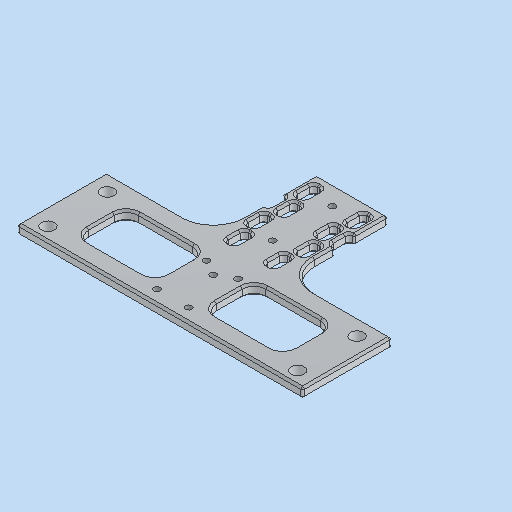
# Autodesk Inventor part: MM0948AN110_G01_101
Saved by Autodesk Inventor 2023.3 (Build 273359000, 359)
## iProperties
Created: 2024-06-12
Part Number: MM0948AN110_G01_101
Material: 3.3547 AlMg4,5Mn0,7 - AW 5083
Description: =<RBPARTNOTITLE2>
Document SubType Name: Modeling
Designer: RIC7AN
Mass: 28.6578 g
Surface Area: 161.617 cm^2
Volume: 28.6578 cm^3
Density: 1 g/cm^3
Appearance: Aluminium AnP
RBPARTMADEOF: 5 x 97 x 144 (FM)
RBDRAWINGMISSINGSPEC: --
AnP_Kategorie: 1
RBPARTNOTITLE2: Anfertigungsteil
RBSURFACE: anodised colourless
RBPARTNOTITLE1: manufactured part
RBSURFACE2: eloxiert farblos
AnP_Material: =<Material>
RBMATERIAL: =<Material>
RBMATNO: =<Part Number>
RBPARTNO: SIEHE MNR
MaxAbmaße: 5 x 97 x 144 (FM)
Author: RIC7AN
Keywords: =<RBPARTMADEOF>
Comments: =<RBSURFACE2>
Revision Number: 01
Autodesk Inventor part; units mm, degrees
ref_plane "YZ Plane" through (0, 0, 0) normal (1, 0, 0) x (0, 1, 0)
ref_plane "XZ Plane" through (0, 0, 0) normal (0, 1, 0) x (-1, 0, 0)
ref_plane "XY Plane" through (0, 0, 0) normal (0, 0, 1) x (1, 0, 0)
sketch "Skizze1" plane through (0, 0, 0) normal (0, 0, 1) x (1, 0, 0)
  line L0 (-72, 45) -> (72, 45)
  line L1 (72, 45) -> (72, 0)
  line L2 (72, 0) -> (-72, 0)
  line L3 (-72, 0) -> (-72, 45)
  line L4 (18, 45) -> (-18, 45)
  line L5 (-18, 45) -> (-18, 97)
  line L6 (-18, 97) -> (18, 97)
  line L7 (18, 97) -> (18, 45)
  line L8 (0, 116.4) -> (0, -19.4) projected
  line L9 (-100.8, 0) -> (100.8, 0) projected
  line L10 (-18, 80) -> (-15.5, 80)
  line L11 (-15.5, 80) -> (-15.5, 70)
  line L12 (-15.5, 70) -> (-18, 70)
  line L13 (-18, 70) -> (-18, 80)
  line L14 (18, 80) -> (15.5, 80)
  line L15 (15.5, 80) -> (15.5, 70)
  line L16 (15.5, 70) -> (18, 70)
  line L17 (18, 70) -> (18, 80)
  point P0 (0, 0)
  point P1 (-18, 45)
  point P2 (-15.5, 75)
  dimension "d0" = 144
  dimension "d1" = 45
  dimension "d2" = 52
  dimension "d3" = 36
  dimension "d65" = 2.5
  dimension "d66" = 10
  dimension "d67" = 22
  constraints: 32 end point, 8 parallel, 4 horizontal, 4 perpendicular, 3 collinear, 3 point on line, 1 midpoint, 3 other
  measures "d0" distance of L1.end L2.end
  measures "d1" distance of L2.end L0.start
  measures "d2" distance of L6.end L4.start
  measures "d3" distance of L5.end L6.end
  measures "d65" distance of L10.start L10.end
  measures "d66" distance of L10.end L11.end
  measures "d67" distance from line of L6 point (-15.5, 75)
extrude "Extrusion1" add sketch "Skizze1" along normal blind 5 contours L0 L8 L2 L3 | L5 L12 L11 L10 L6 L8 L0 | L8 L6 L7 L14 L15 L16 L0 | L0 L1 L2 L8
fillet "Rundung1" radius 15 2 edges at (-18, 45, 2.5) (18, 45, 2.5)
sketch "Skizze2" plane through (0, 0, 5) normal (0, 0, 1) x (1, 0, 0)
  line L0 (0, 116.4) -> (0, -19.4) projected
  line L1 (-33, 45) -> (-72, 45) projected
  point P0 (0, 0)
  point P1 (-63, 36.5)
  point P2 (-63, 6.5)
  point P3 (63, 36.5)
  point P4 (63, 6.5)
  dimension "d10" = 30
  dimension "d11" = 126
  dimension "d69" = 8.5
  constraints: 2 symmetric about line, 2 vertical alignment
  measures "d10" distance of point (-63, 6.5) point (-63, 36.5)
  measures "d11" distance of point (63, 36.5) point (-63, 36.5)
  measures "d69" distance from line of point (-63, 36.5) L1
hole "Bohrung1" at (-63, 36.5, 5) at (-63, 6.5, 5) at (63, 36.5, 5) at (63, 6.5, 5) direction (0, 0, -1) diameter 6.6 end through all clearance for "Inbusschraube ISO 4762  versenkt" size "M6" standard "ISO"
sketch "Skizze3" plane through (0, 0, 5) normal (0, 0, 1) x (1, 0, 0)
  line L0 (0, 116.4) -> (0, -19.4) projected
  line L1 (18, 97) -> (-18, 97) projected
  point P0 (0, 0)
  point P1 (0, 87)
  point P2 (0, 57)
  point P3 (0, 27)
  dimension "d21" = 30
  dimension "d22" = 30
  dimension "d70" = 10
  constraints: 3 point on line
  measures "d21" distance of point (0, 57) point (0, 87)
  measures "d22" distance of point (0, 27) point (0, 57)
  measures "d70" distance from line of point (0, 87) L1
hole "Bohrung2" at (0, 87, 5) at (0, 57, 5) at (0, 27, 5) direction (0, 0, -1) diameter 3.242 end through all thread size "M4x0.7" designation "M4" class "6H" standard "ISO Metric profile"
sketch "Skizze4" plane through (0, 0, 5) normal (0, 0, 1) x (1, 0, 0)
  line L0 (-15, 92.5) -> (-10, 92.5)
  line L1 (-10, 92.5) -> (-10, 82.5)
  line L2 (-10, 82.5) -> (-15, 82.5)
  line L3 (-15, 82.5) -> (-15, 92.5)
  line L4 (10, 92.5) -> (15, 92.5)
  line L5 (15, 92.5) -> (15, 82.5)
  line L6 (15, 82.5) -> (10, 82.5)
  line L7 (10, 82.5) -> (10, 92.5)
  line L8 (15, 67.5) -> (10, 67.5)
  line L9 (10, 67.5) -> (10, 57.5)
  line L10 (10, 57.5) -> (15, 57.5)
  line L11 (15, 57.5) -> (15, 67.5)
  line L12 (-10, 67.5) -> (-15, 67.5)
  line L13 (-15, 67.5) -> (-15, 57.5)
  line L14 (-15, 57.5) -> (-10, 57.5)
  line L15 (-10, 57.5) -> (-10, 67.5)
  line L16 (0, 116.4) -> (0, -19.4) projected
  line L17 (-52, 35) -> (-12.5, 35)
  line L18 (-12.5, 35) -> (-12.5, 10)
  line L19 (-12.5, 10) -> (-52, 10)
  line L20 (-52, 10) -> (-52, 35)
  line L21 (12.5, 35) -> (52, 35)
  line L22 (52, 35) -> (52, 10)
  line L23 (52, 10) -> (12.5, 10)
  line L24 (12.5, 10) -> (12.5, 35)
  line L25 (-12.5, 80) -> (-7.5, 80)
  line L26 (-7.5, 80) -> (-7.5, 70)
  line L27 (-7.5, 70) -> (-12.5, 70)
  line L28 (-12.5, 70) -> (-12.5, 80)
  line L29 (12.5, 80) -> (7.5, 80)
  line L30 (7.5, 80) -> (7.5, 70)
  line L31 (7.5, 70) -> (12.5, 70)
  line L32 (12.5, 70) -> (12.5, 80)
  line L33 (-12.5, 55) -> (-7.5, 55)
  line L34 (-7.5, 55) -> (-7.5, 45)
  line L35 (-7.5, 45) -> (-12.5, 45)
  line L36 (-12.5, 45) -> (-12.5, 55)
  line L37 (7.5, 55) -> (12.5, 55)
  line L38 (12.5, 55) -> (12.5, 45)
  line L39 (12.5, 45) -> (7.5, 45)
  line L40 (7.5, 45) -> (7.5, 55)
  circle A0 centre (-63, 6.5) radius 3.3 projected
  line L41 (-72, 0) -> (72, 0) projected
  point P0 (0, 0)
  dimension "d30" = 20
  dimension "d31" = 5
  dimension "d32" = 10
  dimension "d34" = 15
  dimension "d35" = 10
  dimension "d40" = 25
  dimension "d45" = 5
  dimension "d46" = 10
  dimension "d48" = 10
  dimension "d49" = 15
  dimension "d50" = 15
  dimension "d51" = 2.5
  dimension "d55" = 86
  dimension "d71" = 25
  dimension "d72" = 39.5
  dimension "d73" = 10
  constraints: 80 end point, 20 parallel, 12 collinear, 10 horizontal, 10 perpendicular, 3 point on line, 9 other
  measures "d30" distance between parallel lines of L7 L1
  measures "d31" distance of L0.start L0.end
  measures "d32" distance of L2.end L0.start
  measures "d34" distance between parallel lines of L12 L2
  measures "d35" distance of L12.end L13.end
  measures "d40" distance between parallel lines of L24 L18
  measures "d45" distance of L25.start L25.end
  measures "d46" distance of L27.end L25.start
  measures "d48" distance of L35.end L33.start
  measures "d49" distance between parallel lines of L30 L26
  measures "d50" distance between parallel lines of L33 L27
  measures "d51" distance between parallel lines of L25 L2
  measures "d55" distance from line of A0.centre L0
  measures "d71" distance of L19.end L17.start
  measures "d72" distance of L17.start L17.end
  measures "d73" distance between parallel lines of L41 L19
extrude "Extrusion2" cut sketch "Skizze4" against normal through all contours L0 L1 L2 L3 | L4 L5 L6 L7 | L11 L10 L9 L8 | L15 L14 L13 L12 | L17 L18 L19 L20 | L21 L22 L23 L24 | L25 L26 L27 L28 | L32 L31 L30 L29 | L33 L34 L35 L36 | L37 L38 L39 L40
fillet "Rundung2" radius 2 36 edges at (-15, 92.5, 2.5) (-10, 92.5, 2.5) (10, 92.5, 2.5) (15, 92.5, 2.5) (-15, 67.5, 2.5) (-10, 67.5, 2.5) (10, 67.5, 2.5) (15, 67.5, 2.5) (15, 57.5, 2.5) (10, 57.5, 2.5) (-10, 57.5, 2.5) (-15, 57.5, 2.5) (15, 82.5, 2.5) (10, 82.5, 2.5) (-10, 82.5, 2.5) (-15, 82.5, 2.5) (12.5, 80, 2.5) (7.5, 80, 2.5) (7.5, 70, 2.5) (12.5, 70, 2.5) (7.5, 55, 2.5) (12.5, 55, 2.5) (12.5, 45, 2.5) (7.5, 45, 2.5) (-7.5, 45, 2.5) (-12.5, 45, 2.5) (-12.5, 55, 2.5) (-7.5, 55, 2.5) (-7.5, 80, 2.5) (-12.5, 80, 2.5) (-12.5, 70, 2.5) (-7.5, 70, 2.5) (-15.5, 70, 2.5) (-15.5, 80, 2.5) (15.5, 80, 2.5) (15.5, 70, 2.5)
fillet "Rundung3" radius 6 8 edges at (-52, 35, 2.5) (-52, 10, 2.5) (-12.5, 10, 2.5) (-12.5, 35, 2.5) (12.5, 35, 2.5) (12.5, 10, 2.5) (52, 10, 2.5) (52, 35, 2.5)
sketch "Skizze5" plane through (0, 0, 5) normal (0, 0, 1) x (1, 0, 0)
  line L0 (0, 116.4) -> (0, -19.4) projected
  line L1 (-100.8, 0) -> (100.8, 0) projected
  circle A0 centre (-63, 6.5) radius 3.3 projected
  point P0 (0, 0)
  point P1 (-8, 31.5)
  point P2 (-8, 6.5)
  point P3 (8, 6.5)
  point P4 (8, 31.5)
  dimension "d56" = 16
  dimension "d57" = 25
  constraints: 2 symmetric about line, 1 horizontal alignment, 1 vertical alignment
  measures "d56" distance of point (8, 6.5) point (-8, 6.5)
  measures "d57" distance of point (-8, 6.5) point (-8, 31.5)
hole "Bohrung3" at (-8, 31.5, 5) at (-8, 6.5, 5) at (8, 6.5, 5) at (8, 31.5, 5) direction (0, 0, -1) diameter 3.242 end through all thread size "M4x0.7" designation "M4" class "6H" standard "ISO Metric profile"
fillet "Rundung4" radius 1 10 edges at (-18, 80, 2.5) (-18, 70, 2.5) (18, 70, 2.5) (18, 80, 2.5) (-72, 0, 2.5) (72, 45, 2.5) (72, 0, 2.5) (-72, 45, 2.5) (-18, 97, 2.5) (18, 97, 2.5)
chamfer "Fase3" distance 1 angle 45 204 edges at (52, 45, 0) (18, 64.521, 0) (17.7638, 69.6875, 0) (17.7638, 80.3125, 0) (17.7071, 96.7071, 0) (15.5, 75, 0) (18, 88.479, 0) (0, 97, 0) (-17.7071, 96.7071, 0) (-18, 88.479, 0) (-17.7638, 80.3125, 0) (-17.7638, 69.6875, 0) (-15.5, 75, 0) (-18, 64.521, 0) (-52, 45, 0) (-71.7071, 44.7071, 0) (-72, 22.5, 0) (-71.7071, 0.2929, 0) (0, 0, 0) (71.7071, 0.2929, 0) (72, 22.5, 0) (71.7071, 44.7071, 0) (52, 45, 5) (18, 64.521, 5) (17.7638, 69.6875, 5) (17.7638, 80.3125, 5) (17.7071, 96.7071, 5) (15.5, 75, 5) (18, 88.479, 5) (0, 97, 5) (-17.7071, 96.7071, 5) (-18, 88.479, 5) (-17.7638, 80.3125, 5) (-17.7638, 69.6875, 5) (-15.5, 75, 5) (-18, 64.521, 5) (-52, 45, 5) (-71.7071, 44.7071, 5) (-72, 22.5, 5) (-71.7071, 0.2929, 5) (0, 0, 5) (71.7071, 0.2929, 5) (72, 22.5, 5) (71.7071, 44.7071, 5) (14.4142, 83.0858, 0) (12.5, 82.5, 0) (10.5858, 83.0858, 0) (10, 87.5, 0) (10.5858, 91.9142, 0) (12.5, 92.5, 0) (14.4142, 91.9142, 0) (15, 87.5, 0) (10, 87.5, 5) (10.5858, 91.9142, 5) (12.5, 92.5, 5) (14.4142, 91.9142, 5) (15, 87.5, 5) (14.4142, 83.0858, 5) (12.5, 82.5, 5) (10.5858, 83.0858, 5) (8.0858, 70.5858, 5) (10, 70, 5) (11.9142, 70.5858, 5) (12.5, 75, 5) (11.9142, 79.4142, 5) (10, 80, 5) (8.0858, 79.4142, 5) (7.5, 75, 5) (10, 70, 0) (11.9142, 70.5858, 0) (12.5, 75, 0) (11.9142, 79.4142, 0) (10, 80, 0) (8.0858, 79.4142, 0) (7.5, 75, 0) (8.0858, 70.5858, 0) (12.5, 57.5, 5) (10.5858, 58.0858, 5) (10, 62.5, 5) (10.5858, 66.9142, 5) (12.5, 67.5, 5) (14.4142, 66.9142, 5) (15, 62.5, 5) (14.4142, 58.0858, 5) (14.4142, 58.0858, 0) (12.5, 57.5, 0) (10.5858, 58.0858, 0) (10, 62.5, 0) (10.5858, 66.9142, 0) (12.5, 67.5, 0) (14.4142, 66.9142, 0) (15, 62.5, 0) (8.0858, 45.5858, 5) (10, 45, 5) (11.9142, 45.5858, 5) (12.5, 50, 5) (11.9142, 54.4142, 5) (10, 55, 5) (8.0858, 54.4142, 5) (7.5, 50, 5) (10, 45, 0) (11.9142, 45.5858, 0) (12.5, 50, 0) (11.9142, 54.4142, 0) (10, 55, 0) (8.0858, 54.4142, 0) (7.5, 50, 0) (8.0858, 45.5858, 0) (-12.5, 82.5, 5) (-14.4142, 83.0858, 5) (-15, 87.5, 5) (-14.4142, 91.9142, 5) (-12.5, 92.5, 5) (-10.5858, 91.9142, 5) (-10, 87.5, 5) (-10.5858, 83.0858, 5) (-10.5858, 83.0858, 0) (-12.5, 82.5, 0) (-14.4142, 83.0858, 0) (-15, 87.5, 0) (-14.4142, 91.9142, 0) (-12.5, 92.5, 0) (-10.5858, 91.9142, 0) (-10, 87.5, 0) (-10, 70, 5) (-11.9142, 70.5858, 5) (-12.5, 75, 5) (-11.9142, 79.4142, 5) (-10, 80, 5) (-8.0858, 79.4142, 5) (-7.5, 75, 5) (-8.0858, 70.5858, 5) (-8.0858, 70.5858, 0) (-10, 70, 0) (-11.9142, 70.5858, 0) (-12.5, 75, 0) (-11.9142, 79.4142, 0) (-10, 80, 0) (-8.0858, 79.4142, 0) (-7.5, 75, 0) (-12.5, 57.5, 5) (-14.4142, 58.0858, 5) (-15, 62.5, 5) (-14.4142, 66.9142, 5) (-12.5, 67.5, 5) (-10.5858, 66.9142, 5) (-10, 62.5, 5) (-10.5858, 58.0858, 5) (-10.5858, 58.0858, 0) (-12.5, 57.5, 0) (-14.4142, 58.0858, 0) (-15, 62.5, 0) (-14.4142, 66.9142, 0) (-12.5, 67.5, 0) (-10.5858, 66.9142, 0) (-10, 62.5, 0) (-11.9142, 45.5858, 5) (-10, 45, 5) (-8.0858, 45.5858, 5) (-7.5, 50, 5) (-8.0858, 54.4142, 5) (-10, 55, 5) (-11.9142, 54.4142, 5) (-12.5, 50, 5) (-10, 45, 0) (-8.0858, 45.5858, 0) (-7.5, 50, 0) (-8.0858, 54.4142, 0) (-10, 55, 0) (-11.9142, 54.4142, 0) (-12.5, 50, 0) (-11.9142, 45.5858, 0) (14.2574, 11.7574, 5) (32.25, 10, 5) (50.2426, 11.7574, 5) (52, 22.5, 5) (50.2426, 33.2426, 5) (32.25, 35, 5) (14.2574, 33.2426, 5) (12.5, 22.5, 5) (14.2574, 11.7574, 0) (12.5, 22.5, 0) (14.2574, 33.2426, 0) (32.25, 35, 0) (50.2426, 33.2426, 0) (52, 22.5, 0) (50.2426, 11.7574, 0) (32.25, 10, 0) (-32.25, 10, 5) (-50.2426, 11.7574, 5) (-52, 22.5, 5) (-50.2426, 33.2426, 5) (-32.25, 35, 5) (-14.2574, 33.2426, 5) (-12.5, 22.5, 5) (-14.2574, 11.7574, 5) (-32.25, 10, 0) (-14.2574, 11.7574, 0) (-12.5, 22.5, 0) (-14.2574, 33.2426, 0) (-32.25, 35, 0) (-50.2426, 33.2426, 0) (-52, 22.5, 0) (-50.2426, 11.7574, 0)
equation "\"d35\" = d32"
equation "\"d45\" = d31"
equation "\"d46\" = d32"
equation "\"d48\" = d32"
equation "\"d50\" = d34"
